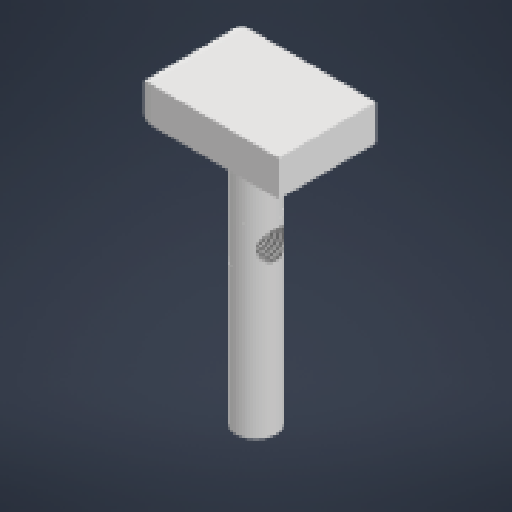
# Autodesk Inventor part: truc_khop2
Saved by Autodesk Inventor 2026.2 (Build 302298000, 298)
## iProperties
Created: 2026-04-03
Part Number: truc_khop2
Material: Generic
Document SubType Name: Modeling
Designer: thita
Density: 1 g/cm^3
Appearance: Default
Author: thita
Autodesk Inventor part; units mm, degrees
ref_plane "YZ Plane" through (0, 0, 0) normal (1, 0, 0) x (0, 1, 0)
ref_plane "Work Plane1" through (-0.2, 35.5, -6.8) normal (0, 1, 0) x (0, 0, 1)
sketch "Sketch1" plane through (0, 0, 0) normal (0, 1, 0) x (-1, 0, 0)
  circle A0 centre (0, 0) radius 2.8
  dimension "d0" = 5.6
  constraints: 1 centre point, 1 coincident
  measures "d0" diameter of A0
extrude "Extrusion1" add sketch "Sketch1" along normal up to surface (35.5 mm away)
sketch "Sketch2" plane through (0, 35.5, 0) normal (0, 1, 0) x (1, 0, 0)
  line L0 (10, -6.8) -> (10, 6.8)
  line L1 (10, 6.8) -> (-10, 6.8)
  line L2 (-10, 6.8) -> (-10, -6.8)
  line L3 (-10, -6.8) -> (10, -6.8)
  line L4 (10, -6.8) -> (-10, 6.8) construction
  line L5 (10, 6.8) -> (-10, -6.8) construction
  point P0 (0, 0)
  dimension "d3" = 13.6
  dimension "d4" = 20
  constraints: 12 end point, 2 midpoint, 2 parallel, 1 perpendicular, 1 vertical
  measures "d3" distance of L0.start L0.end
  measures "d4" distance of L1.end L0.end
extrude "Extrusion2" add sketch "Sketch2" along normal blind 5
sketch "Sketch3" plane through (0, 0, 0) normal (0, -1, 0) x (1, 0, 0)
  circle A0 centre (0, 0) radius 2
  dimension "d7" = 4
  constraints: 1 centre point, 1 coincident
  measures "d7" diameter of A0
extrude "Extrusion3" cut sketch "Sketch3" against normal blind 3
sketch "Sketch6" plane through (0, 0, 0) normal (0, 0, 1) x (1, 0, 0)
  line L0 (2.8, 0) -> (-2.8, 0) projected
  line L1 (-2.8, 20) -> (0, 20)
  line L2 (0, 20) -> (0, 26)
  line L3 (0, 26) -> (2.8, 26)
  point P0 (0, 0)
  dimension "d20" = 20
  dimension "d24" = 6
  constraints: 6 end point, 2 perpendicular, 1 horizontal
  measures "d20" distance of L0.end L1.start
  measures "d24" distance of L1.end L2.end
split body "Split2" sketch "Sketch6" result two bodies curves L1 L2 L3 first body at (-3.3333, 40, -2.2667)
sketch "Sketch7" plane through (0, 0, 0) normal (1, 0, 0) x (0, 1, 0)
  line L0 (26, -2.8) -> (26, 2.8) projected
  line L1 (0, 2.8) -> (26, 2.8) projected
  line L2 (26, -2.8) -> (20, -2.8)
  line L3 (20, -2.8) -> (20, 2.8)
  line L4 (20, 2.8) -> (26, 2.8)
  line L5 (26, 2.8) -> (26, -2.8)
  circle A0 centre (23, 0) radius 2
  point P0 (0, 0)
  dimension "d25" = 6
  dimension "d26" = 4
  constraints: 8 end point, 2 parallel, 1 centre point, 1 horizontal, 1 perpendicular, 1 point on line
  measures "d25" distance of L3.end L4.end
  measures "d26" diameter of A0
extrude "Extrusion5" cut sketch "Sketch7" along normal mid plane 10 contours A0 bodies 3 2
thread "Thread2" size "M4x0.7" class "6H" standard "ISO Metric profile" length 12
thread "Thread3" size "M4x0.7" class "6H" standard "ISO Metric profile" length 12
sketch "Sketch8" plane through (-10, 35.5, 6.8) normal (0, 0, 1) x (1, 0, 0)
  line L0 (20, 0) -> (20, 5) projected
  line L1 (0, 5) -> (20, 5)
  line L2 (20, 5) -> (20, 0)
  line L3 (20, 0) -> (0, 0)
  line L4 (0, 0) -> (0, 5)
  point P0 (10, -35.5)
  constraints: 8 end point, 2 parallel, 1 horizontal, 1 perpendicular
ref_plane "Work Plane2" through (-0.2097, 28.4747, 7.8) normal (0, 0, 1) x (1, 0, 0)
extrude "Extrusion6" add sketch "Sketch8" along normal up to surface (1 mm away) bodies 2
body "Solid4"
body "Solid5"
